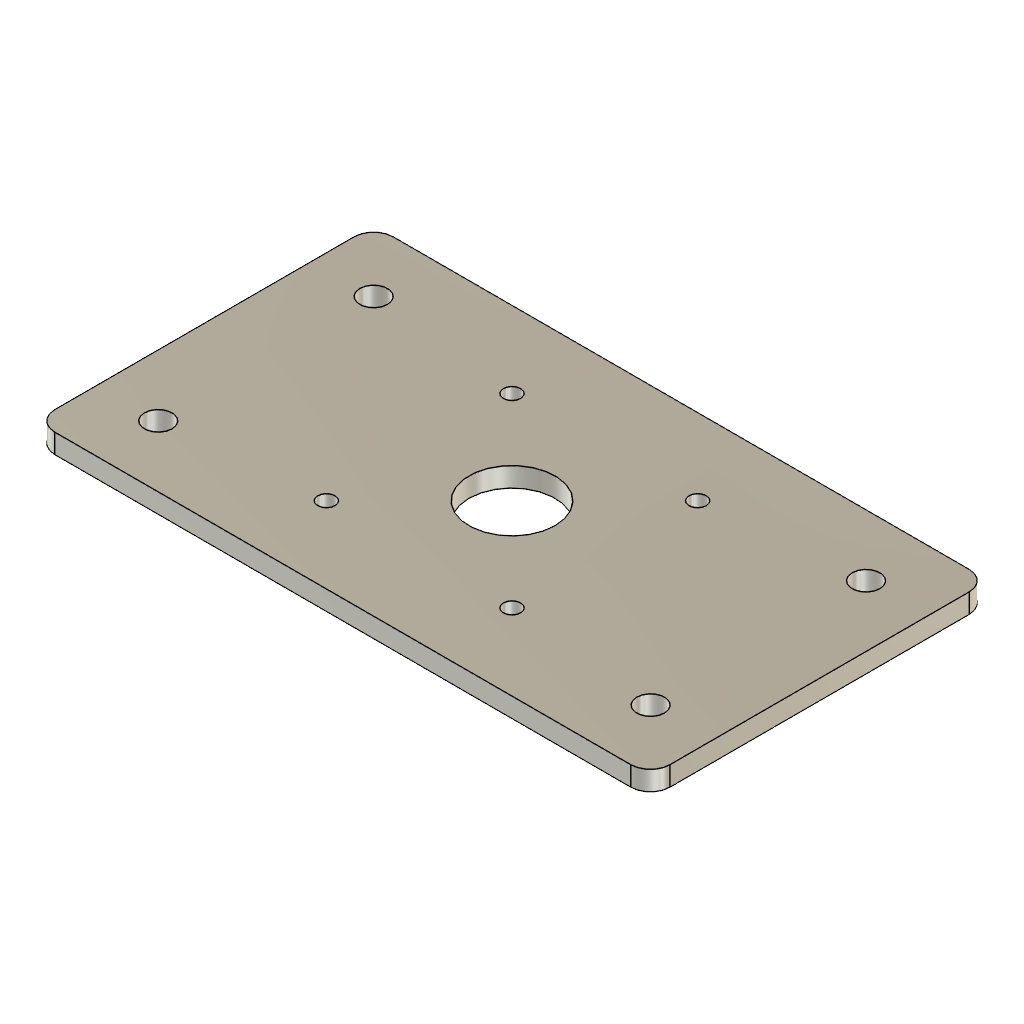
Motor Mount A11 (Autodesk Fusion 360 archive; units mm, degrees)
design "Motor Mount A11"
part number: 2026-11-18-16-25-44-379
Autodesk Fusion 360 part; units mm, degrees
sketch "Sketch1" plane through (0, 0, 0) normal (0, 0, 1) x (1, 0, 0)
  line L0 (6.35, 0) -> (193.548, 0)
  line L1 (199.898, 6.35) -> (199.898, 103.632)
  line L2 (193.548, 109.982) -> (6.35, 109.982)
  line L3 (0, 103.632) -> (0, 6.35)
  arc A0 (6.35, 109.982) -> (0, 103.632) centre (6.35, 103.632) ccw
  arc A1 (0, 6.35) -> (6.35, 0) centre (6.35, 6.35) ccw
  arc A2 (193.548, 0) -> (199.898, 6.35) centre (193.548, 6.35) ccw
  arc A3 (199.898, 103.632) -> (193.548, 109.982) centre (193.548, 103.632) ccw
  point P0 (199.898, 0)
  point P1 (0, 109.982)
  dimension "d4" = 199.898
  dimension "d5" = 109.982
  dimension "d6" = 6.35
  constraint horizontal L0
  constraint vertical L1
  constraint horizontal L2
  constraint vertical L3
  constraint coincident P1 L2
  constraint coincident P1 L3
  constraint tangent L2 A0
  constraint tangent L3 A0
  constraint coincident origin L0
  constraint coincident origin L3
  constraint tangent L0 A1
  constraint tangent L3 A1
  constraint equal A0 A1
  constraint coincident P0 L0
  constraint coincident P0 L1
  constraint tangent L0 A2
  constraint tangent L1 A2
  constraint equal A0 A2
  constraint tangent L1 A3
  constraint tangent L2 A3
  constraint equal A0 A3
  measures "d4" distance of origin P0
  measures "d5" distance of origin P1
  measures "d6" radius of A0
extrude "Extrude1" add sketch "Sketch1" along normal blind 6.35
hole "Hole1" at (99.949, 54.991, 6.35) direction (0, 0, -1) diameter 27.9908 end through all
sketch "Sketch2" plane through (0, 0, 6.35) normal (0, 0, 1) x (-1, 0, 0)
  circle A0 centre (-99.949, -54.991) radius 13.9954
  arc A1 (-199.898, -103.632) -> (-193.548, -109.982) centre (-193.548, -103.632) ccw
  line L0 (-193.548, -109.982) -> (-6.35, -109.982)
  arc A2 (-6.35, -109.982) -> (0, -103.632) centre (-6.35, -103.632) ccw
  line L1 (0, -103.632) -> (0, -6.35)
  arc A3 (0, -6.35) -> (-6.35, 0) centre (-6.35, -6.35) ccw
  line L2 (-6.35, 0) -> (-193.548, 0)
  arc A4 (-193.548, 0) -> (-199.898, -6.35) centre (-193.548, -6.35) ccw
  line L3 (-199.898, -6.35) -> (-199.898, -103.632)
  circle A5 centre (-69.7865, -85.1535) radius 2.794
  circle A6 centre (-130.1115, -85.1535) radius 2.794
  circle A7 centre (-130.1115, -24.8285) radius 2.794
  circle A8 centre (-69.7865, -24.8285) radius 2.794
  point P0 (-130.1115, -85.1535)
  point P1 (-69.7865, -24.8285)
  point P2 (-130.1115, -24.8285)
  dimension "d13" = 5.588
  dimension "d14" = 30.1625
  dimension "d15" = 30.1625
  dimension "d18" = -60.325
  dimension "d19" = 60.325
  dimension "d20" = 5.588
  dimension "d21" = 5.588
  dimension "d22" = 5.588
  constraint coincident P0 A6.centre
  constraint coincident P2 A7.centre
  constraint coincident P1 A8.centre
  measures "d13" diameter of A5
  measures "d14" horizontal distance of A0.centre A5.centre
  measures "d15" vertical distance of A0.centre A5.centre
  measures "d20" diameter of A6
  measures "d21" diameter of A7
  measures "d22" diameter of A8
extrude "Extrude2" cut sketch "Sketch2" against normal through all contours A5 | A6 | A7 | A8
sketch "Sketch3" plane through (0, 0, 6.35) normal (0, 0, 1) x (-1, 0, 0)
  arc A0 (-199.898, -103.632) -> (-193.548, -109.982) centre (-193.548, -103.632) ccw
  line L0 (-193.548, -109.982) -> (-6.35, -109.982)
  arc A1 (-6.35, -109.982) -> (0, -103.632) centre (-6.35, -103.632) ccw
  line L1 (0, -103.632) -> (0, -6.35)
  arc A2 (0, -6.35) -> (-6.35, 0) centre (-6.35, -6.35) ccw
  line L2 (-6.35, 0) -> (-193.548, 0)
  arc A3 (-193.548, 0) -> (-199.898, -6.35) centre (-193.548, -6.35) ccw
  line L3 (-199.898, -6.35) -> (-199.898, -103.632)
  circle A4 centre (-99.949, -54.991) radius 13.9954
  circle A5 centre (-69.7865, -24.8285) radius 2.794
  circle A6 centre (-69.7865, -85.1535) radius 2.794
  circle A7 centre (-130.1115, -24.8285) radius 2.794
  circle A8 centre (-130.1115, -85.1535) radius 2.794
  circle A9 centre (-19.9898, -89.9922) radius 4.4958
  circle A10 centre (-179.9844, -89.9922) radius 4.4958
  circle A11 centre (-179.9844, -19.9898) radius 4.4958
  circle A12 centre (-19.9898, -19.9898) radius 4.4958
  point P0 (-179.9844, -89.9922)
  point P1 (-19.9898, -19.9898)
  point P2 (-179.9844, -19.9898)
  dimension "d24" = 8.9916
  dimension "d25" = 19.9898
  dimension "d26" = 19.9898
  dimension "d29" = -159.9946
  dimension "d30" = 70.0024
  dimension "d31" = 8.9916
  dimension "d32" = 8.9916
  dimension "d33" = 8.9916
  constraint coincident P0 A10.centre
  constraint coincident P2 A11.centre
  constraint coincident P1 A12.centre
  measures "d24" diameter of A9
  measures "d25" distance of L0 A9.centre
  measures "d26" distance of L1 A9.centre
  measures "d31" diameter of A10
  measures "d32" diameter of A11
  measures "d33" diameter of A12
extrude "Extrude3" cut sketch "Sketch3" against normal through all contours A9 | A10 | A11 | A12
equation "Length = 7.87 in"
equation "Width = 4.33 in"
equation "Thickness = 0.25 in"
equation "d4 = Length"
equation "d5 = Width"
equation "d7 = Thickness"
